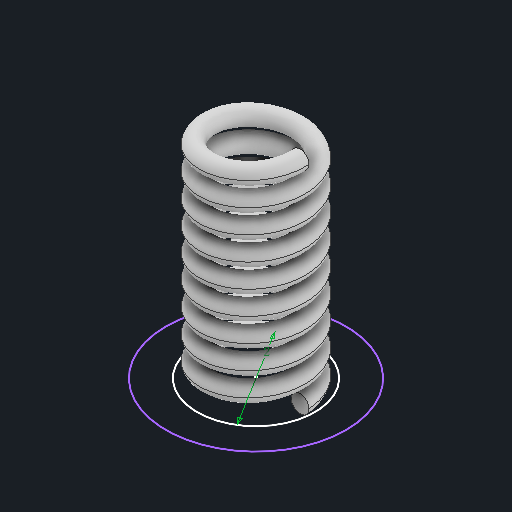
# Autodesk Inventor part: 扭簧
Saved by Autodesk Inventor 2025 (Build 290162000, 162)
## iProperties
Created: 2025-08-27
Part Number: 扭簧
Material: 常规
Document SubType Name: Modeling
Designer: HZD
Density: 1 g/cm^3
Appearance: 默认
Author: HZD
Autodesk Inventor part; units mm, degrees
ref_plane "YZ Plane" through (0, 0, 0) normal (1, 0, 0) x (0, 1, 0)
ref_plane "XZ Plane" through (0, 0, 0) normal (0, 1, 0) x (-1, 0, 0)
ref_plane "XY Plane" through (0, 0, 0) normal (0, 0, 1) x (1, 0, 0)
sketch "草图3" plane through (0, 0, 0) normal (0, 0, 1) x (1, 0, 0)
  line L0 (0, 0) -> (0.75, 0)
  circle A0 centre (0.75, 0) radius 0.15
  dimension "d3" = 0.75
  dimension "d4" = 0.3
  constraints: 2 coincident, 2 end point, 1 centre point, 1 horizontal
  measures "d3" distance of point (0, 0) L0.end
  measures "d4" diameter of A0
coil "螺旋扫掠1" sketch "草图3" operation add axis through (0, -10, 0) along (0, 1, 0) pitch 0.4 turns 9 hand right
sketch "草图4" plane through (0, 0, 0) normal (0, 1, 0) x (-1, 0, 0)
  circle A0 centre (0, 0) radius 1
  circle A1 centre (0, 0) radius 1.5284
  dimension "d14" = 2
  constraints: 2 centre point, 2 coincident
  measures "d14" diameter of A0
sketch "草图5" plane through (0.75, 3.6, 0) normal (0, 0, -1) x (-1, 0, 0)
  circle A0 centre (0, 0) radius 0.15 projected
  point P0 (0.75, -3.6)
  point P1 (-0.15, 0)
  constraints: 1 horizontal alignment
